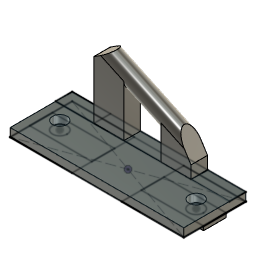
Retractor_Mount_Slanted (Autodesk Fusion 360 design; units mm, degrees)
Autodesk Fusion 360 part; units mm, degrees
sketch "Sketch1" plane through (0, 0, 0) normal (0, 0, 1) x (1, 0, 0)
  line L0 (21, 7.5) -> (-21, 7.5)
  line L1 (-21, 7.5) -> (-21, -7.5)
  line L2 (-21, -7.5) -> (21, -7.5)
  line L3 (21, -7.5) -> (21, 7.5)
  line L4 (21, 7.5) -> (-21, -7.5) construction
  line L5 (-21, 7.5) -> (21, -7.5) construction
  line L6 (-21, 7.5) -> (-6, 7.5)
  line L7 (-6, 7.5) -> (-6, -7.5)
  line L8 (-6, -7.5) -> (-21, -7.5)
  line L9 (-21, -7.5) -> (-21, 7.5)
  line L10 (21, 7.5) -> (6, 7.5)
  line L11 (6, 7.5) -> (6, -7.5)
  line L12 (6, -7.5) -> (21, -7.5)
  line L13 (21, -7.5) -> (21, 7.5)
  line L14 (-21, 2.75) -> (-6, 2.75)
  line L15 (-6, 2.75) -> (-6, -2.75)
  line L16 (-6, -2.75) -> (-21, -2.75)
  line L17 (-21, -2.75) -> (-21, 2.75)
  line L18 (6, 2.75) -> (21, 2.75)
  line L19 (21, 2.75) -> (21, -2.75)
  line L20 (21, -2.75) -> (6, -2.75)
  line L21 (6, -2.75) -> (6, 2.75)
  circle A0 centre (-16.5, 0) radius 1.75
  circle A1 centre (16.5, 0) radius 1.75
  dimension "d1" = 12
  dimension "d2" = 15
  dimension "d3" = 15
  dimension "d4" = 15
  dimension "d5" = 5.5
  dimension "d6" = 5.5
  dimension "d7" = 4.75
  dimension "d8" = 4.75
  dimension "d9" = 3.5
  dimension "d10" = 3.5
  dimension "d11" = 2.75
  dimension "d12" = 2.75
  dimension "d13" = 4.5
  dimension "d14" = 4.5
  constraint horizontal L0
  constraint perpendicular L0 L1
  constraint parallel L0 L2
  constraint parallel L1 L3
  constraint coincident L4 origin
  constraint coincident L5 origin
  constraint horizontal L6
  constraint vertical L7
  constraint horizontal L8
  constraint vertical L9
  constraint coincident L2 L7.end
  constraint horizontal L10
  constraint vertical L11
  constraint horizontal L12
  constraint vertical L13
  constraint coincident L2 L11.end
  constraint horizontal L14
  constraint vertical L15
  constraint horizontal L16
  constraint vertical L17
  constraint coincident L7 L15.end
  constraint coincident L1 L14.start
  constraint horizontal L18
  constraint vertical L19
  constraint horizontal L20
  constraint vertical L21
  constraint coincident L3 L19.end
  constraint coincident L11 L18.start
  measures "d1" distance of L7 L11
  measures "d2" distance of L7 L9
  measures "d3" distance of L11 L13
  measures "d4" distance of L0 L2
  measures "d5" distance of L14 L16
  measures "d6" distance of L18 L20
  measures "d7" distance of L6 L14
  measures "d8" distance of L0 L18
  measures "d9" diameter of A0
  measures "d10" diameter of A1
  measures "d11" distance of L14 A0.centre
  measures "d12" distance of L18 A1.centre
  measures "d13" distance of L1 A0.centre
  measures "d14" distance of L13 A1.centre
extrude "Extrude1" add sketch "Sketch1" along normal blind 2
extrude "Extrude2" add sketch "Sketch1" against normal blind 1 contours L3 L11 L13 L18 L19 L20 L21 | L1 L7 L9 L14 L15 L16 L17
sketch "Sketch2" plane through (0, 0, 2) normal (0, 0, 1) x (-1, 0, 0)
  circle A0 centre (-16.5, 0) radius 1.75
  circle A1 centre (16.5, 0) radius 1.75
  line L0 (-21, -7.5) -> (21, -7.5)
  line L1 (21, -7.5) -> (21, 7.5)
  line L2 (21, 7.5) -> (-21, 7.5)
  line L3 (-21, 7.5) -> (-21, -7.5)
  line L4 (21, -7.5) -> (-21, -7.5)
  line L5 (-21, -7.5) -> (-21, -3.5)
  line L6 (-21, -3.5) -> (21, -3.5)
  line L7 (21, -3.5) -> (21, -7.5)
  line L8 (11.75, -7.5) -> (11.75, -3.5)
  line L9 (-11.75, -7.5) -> (-11.75, -3.5)
  dimension "d19" = 4
  dimension "d21" = 3
  dimension "d22" = 3
  constraint horizontal L4
  constraint vertical L5
  constraint horizontal L6
  constraint vertical L7
  constraint collinear L1 L7
  constraint collinear L3 L5
  constraint coincident L4 L8.start
  constraint coincident L6 L8.end
  constraint perpendicular L6 L8
  constraint coincident L4 L9.start
  constraint coincident L6 L9.end
  constraint perpendicular L6 L9
  constraint collinear L0 L4
  measures "d19" distance of L4 L6
  measures "d21" distance of A1 L8
  measures "d22" distance of A0 L9
sketch "Sketch6" plane through (0, 7.5, 0) normal (0, 1, 0) x (-1, 0, 0)
  line L0 (-21, 0) -> (21, 0)
  line L1 (21, 0) -> (21, 2)
  line L2 (21, 2) -> (-21, 2)
  line L3 (-21, 2) -> (-21, 0)
extrude "Extrude9" add sketch "Sketch2" along normal blind 18 contours L0 L4 L6 L8 L9
sketch "Sketch8" plane through (0, 3.5, 0) normal (0, -1, 0) x (1, 0, 0)
  line L0 (-11.75, 2) -> (11.75, 2)
  line L1 (11.75, 2) -> (11.75, 20)
  line L2 (11.75, 20) -> (-11.75, 20)
  line L3 (-11.75, 20) -> (-11.75, 2)
  line L4 (-11.75, 20) -> (11.75, 9.0418)
  line L5 (-4.5, 12.2058) -> (4.5, 8.009)
  line L6 (-4.5, 12.2058) -> (-4.5, 2)
  line L7 (4.5, 8.009) -> (4.5, 2)
  dimension "d50" = 25
  dimension "d51" = 9
  dimension "d52" = 7.25
  dimension "d53" = 4
  constraint coincident L2.end L3.start
  constraint coincident L1 L4.end
  constraint parallel L4 L5
  constraint coincident L0 L6.end
  constraint perpendicular L0 L6
  constraint coincident L0 L7.end
  constraint perpendicular L0 L7
  measures "d50" angle of L2 L4
  measures "d51" distance of L6 L7
  measures "d52" distance of L3 L6
  measures "d53" distance of L4 L5
extrude "Extrude10" cut sketch "Sketch8" against normal up to surface (4 mm away) contours L0 L5 L6 L7 | L1 L2 L4
chamfer "Chamfer3" distance 4 angle 45 2 edges at (11.75, 5.5, 9.0418) (-11.75, 5.5, 20) measured on face at (11.75, 6.1667, 4.3473) measured on face at (-3.9167, 4.8333, 16.3473)
fillet "Fillet2" radius 2 4 edges at (0, 7.5, 14.5209) (0, 3.5, 14.5209) (0, 7.5, 10.1074) (0, 3.5, 10.1074)
equation "d3 = d2"
equation "d4 = d2"
equation "d6 = d5"
equation "d7 = d4 / 2 - ( d5 / 2 )"
equation "d8 = d7"
equation "d11 = d5 / 2"
equation "d12 = d11"
equation "d13 = d2 / 2 - 3 mm"
equation "d14 = d13"
equation "d22 = d21"
equation "d48 = Height"
equation "d50 = Angle"
equation "Angle = 25 deg"
equation "Height = 18 mm"
